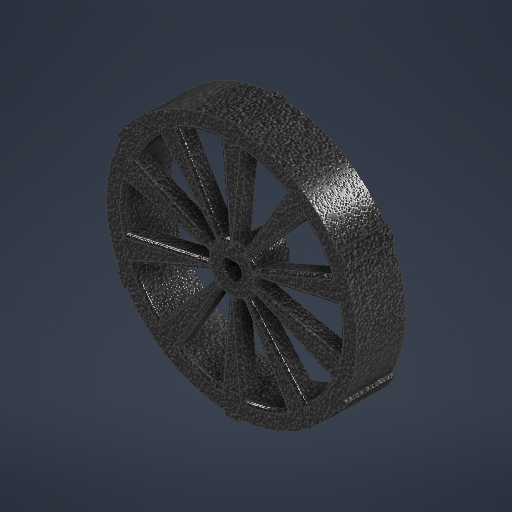
# Autodesk Inventor part: roues_3d_moteur
Saved by Autodesk Inventor 2026 (Build 300175050, 175E)
## iProperties
Created: 2025-05-23
Part Number: roues_3d_moteur
Material: Generisch
Document SubType Name: Modeling
Designer: karle
Density: 1 g/cm^3
Appearance: Vorgabe
Author: karle
Autodesk Inventor part; units mm, degrees
ref_plane "YZ Plane" through (0, 0, 0) normal (1, 0, 0) x (0, 1, 0)
sketch "Skizze1" plane through (0, 0, 0) normal (0, 0, 1) x (1, 0, 0)
  circle A0 centre (0, 0) radius 3.05
  circle A1 centre (0, 0) radius 37.55
  dimension "d0" = 6.1
  dimension "d1" = 75.1
  constraints: 2 centre point, 2 coincident
  measures "d0" diameter of A0
  measures "d1" diameter of A1
extrude "Extrusion1" add sketch "Skizze1" along normal mid plane 14.5
sketch "Skizze2" plane through (0, 0, -7.25) normal (0, 0, -1) x (-1, 0, 0)
  circle A0 centre (0, 0) radius 32.5
  circle A1 centre (0, 0) radius 5
  dimension "d4" = 10
  dimension "d5" = 65
  constraints: 2 centre point, 2 coincident
  measures "d4" diameter of A1
  measures "d5" diameter of A0
extrude "Extrusion2" cut sketch "Skizze2" against normal blind 10
sketch "Skizze3" plane through (0, 0, 7.25) normal (0, 0, 1) x (1, 0, 0)
  circle A0 centre (0, 0) radius 3.05 projected
  arc A1 (-7.4013, 1.213) -> (-7.4013, -1.213) centre (0, 0) ccw
  arc A2 (-31.8174, 6.6259) -> (-31.8174, -6.6259) centre (0, 0) ccw
  line L0 (-31.8174, 6.6259) -> (-7.4013, 1.213)
  line L1 (-7.4013, -1.213) -> (-31.8174, -6.6259)
  line L2 (0, 0) -> (-34.8454, 0)
  dimension "d8" = 65
  dimension "d9" = 15
  dimension "d12" = 25
  constraints: 6 end point, 4 point on circle, 2 centre point, 2 coincident, 1 horizontal, 1 other
  measures "d8" diameter of A2
  measures "d9" diameter of A1
  measures "d12" angle of L0 L1
extrude "Extrusion3" cut sketch "Skizze3" against normal blind 5 contours A1 L1 A2 L2 | L2 A2 L0 A1
pattern_circular "Runde Anordnung1" count 10 over 360 about axis through (0, 0, -10) along (0, 0, 1) of "Extrusion3"
fillet "Rundung1" radius 1 40 edges at (-19.6093, 3.9194, 7.25) (-32.5, 0, 7.25) (-19.6093, -3.9194, 7.25) (-7.5, 0, 7.25) (-18.1681, 8.3552, 7.25) (-26.2931, 19.103, 7.25) (-13.5605, 14.697, 7.25) (-6.0676, 4.4084, 7.25) (-2.3176, 7.1329, 7.25) (-9.7872, 17.4384, 7.25) (-10.0431, 30.9093, 7.25) (-2.332, 19.8608, 7.25) (2.332, 19.8608, 7.25) (10.0431, 30.9093, 7.25) (9.7872, 17.4384, 7.25) (2.3176, 7.1329, 7.25) (13.5605, 14.697, 7.25) (18.1681, 8.3552, 7.25) (6.0676, 4.4084, 7.25) (26.2931, 19.103, 7.25) (32.5, 0, 7.25) (26.2931, -19.103, 7.25) (18.1681, -8.3552, 7.25) (19.6093, -3.9194, 7.25) (19.6093, 3.9194, 7.25) (7.5, 0, 7.25) (6.0676, -4.4084, 7.25) (13.5605, -14.697, 7.25) (9.7872, -17.4384, 7.25) (2.3176, -7.1329, 7.25) (2.332, -19.8608, 7.25) (10.0431, -30.9093, 7.25) (-2.332, -19.8608, 7.25) (-10.0431, -30.9093, 7.25) (-9.7872, -17.4384, 7.25) (-2.3176, -7.1329, 7.25) (-13.5605, -14.697, 7.25) (-18.1681, -8.3552, 7.25) (-6.0676, -4.4084, 7.25) (-26.2931, -19.103, 7.25)
sketch "Skizze4" plane through (0, 0, -7.25) normal (0, 0, -1) x (-1, 0, 0)
  circle A0 centre (0, 0) radius 5
  circle A1 centre (0, 0) radius 3
  constraints: 2 centre point, 2 coincident
extrude "Extrusion4" cut sketch "Skizze4" against normal blind 2
ref_plane "Arbeitsebene1" through (0, 5, -7.25) normal (0, 1, 0) x (-1, 0, 0)
ref_plane "Arbeitsebene2" through (0, 3.05, 0) normal (0, 1, 0) x (-1, 0, 0)
sketch "Skizze8" plane through (0, 3.05, 0) normal (0, 1, 0) x (-1, 0, 0)
  line L0 (-3.05, -5.25) -> (3.05, -5.25) projected
  line L1 (37.55, 7.25) -> (-37.55, 7.25) projected
  line L2 (1.6585, -5.25) -> (-1.6585, -5.25)
  line L3 (-1.6585, -5.25) -> (-1.6585, 7.25)
  line L4 (-1.6585, 7.25) -> (1.6585, 7.25)
  line L5 (1.6585, 7.25) -> (1.6585, -5.25)
  point P0 (0, 0)
  point P1 (0, 7.25)
  point P2 (-1.6585, -5.25)
  dimension "d36" = 3.317
  dimension "d37" = 1.6585
  constraints: 8 end point, 2 parallel, 2 point on line, 1 horizontal, 1 midpoint, 1 perpendicular
  measures "d36" distance between parallel lines of L5 L3
  measures "d37" distance from line of L3 point (0, 7.25)
extrude "Extrusion5" add sketch "Skizze8" against normal blind 0.5
ref_plane "Arbeitsebene3" through (0, -37.55, 0) normal (0, 1, 0) x (-1, 0, 0)
sketch "Skizze9" plane through (0, -37.55, 0) normal (0, 1, 0) x (-1, 0, 0)
  line L0 (0, -7.25) -> (0, 7.25) projected
  line L1 (-2.6307, 7.25) -> (-0.0409, 7.25) projected
  line L2 (2, -7.2704) -> (-2, -7.2704)
  line L3 (-2, -7.2704) -> (-2, 7.25)
  line L4 (-2, 7.25) -> (2, 7.25)
  line L5 (2, 7.25) -> (2, -7.2704)
  point P0 (0, 0)
  dimension "d40" = 4
  dimension "d41" = 2
  constraints: 8 end point, 2 parallel, 1 horizontal, 1 perpendicular, 1 point on line
  measures "d40" distance between parallel lines of L5 L3
  measures "d41" distance between parallel lines of L3 L0
extrude "Extrusion6" add sketch "Skizze9" along normal mid plane 2
pattern_circular "Runde Anordnung2" count 6 over 360 about axis through (0, 0, -10) along (0, 0, 1) of "Extrusion6"
chamfer "Fasen1" distance 2.5 angle 45 1 edges at (5, 0, 2.75)
